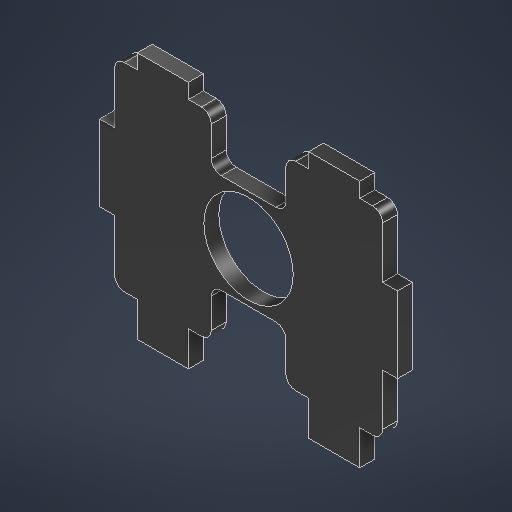
# Autodesk Inventor part: TransmitterFace
Saved by Autodesk Inventor 2027.1 (Build 311270010, 270A)
## iProperties
Created: 2026-10-16
Part Number: TransmitterFace
Material: MDF Medium Density Fiberboard
Document SubType Name: Modeling
Designer: SDS Scholar
Density: 0.8 g/cm^3
Appearance: Glossy - Black
Mass: 5.12957 g
Surface Area: 52.7394 cm^2
Volume: 6.41197 cm^3
Author: SDS Scholar
Autodesk Inventor part; units mm, degrees
ref_plane "YZ Plane" through (0, 0, 0) normal (1, 0, 0) x (0, 1, 0)
ref_plane "XZ Plane" through (0, 0, 0) normal (0, 1, 0) x (-1, 0, 0)
ref_plane "XY Plane" through (0, 0, 0) normal (0, 0, 1) x (1, 0, 0)
sketch "Sketch1" plane through (0, 0, 0) normal (0, 0, 1) x (1, 0, 0)
  line L0 (27, 20) -> (-27, 20)
  line L1 (-27, 20) -> (-27, -20)
  line L2 (-27, -20) -> (27, -20)
  line L3 (27, -20) -> (27, 20)
  circle A0 centre (0, 0) radius 9
  line L4 (7.5, 20) -> (-7.5, 20)
  line L5 (-7.5, 20) -> (-7.5, 10)
  line L6 (-7.5, 10) -> (7.5, 10)
  line L7 (7.5, 10) -> (7.5, 20)
  line L8 (7.5, -20) -> (-7.5, -20)
  line L9 (-7.5, -20) -> (-7.5, -10)
  line L10 (-7.5, -10) -> (7.5, -10)
  line L11 (7.5, -10) -> (7.5, -20)
  line L12 (22.4, 20) -> (12.1, 20)
  line L13 (12.1, 20) -> (12.1, 23)
  line L14 (12.1, 23) -> (22.4, 23)
  line L15 (22.4, 23) -> (22.4, 20)
  line L16 (27, 20) -> (7.5, 20) construction
  line L17 (0, 20) -> (0, -20) construction
  line L18 (22.4, -20) -> (12.1, -20)
  line L19 (12.1, -20) -> (12.1, -27)
  line L20 (12.1, -27) -> (22.4, -27)
  line L21 (22.4, -27) -> (22.4, -20)
  line L22 (27, 7.65) -> (30, 7.65)
  line L23 (30, 7.65) -> (30, -7.65)
  line L24 (30, -7.65) -> (27, -7.65)
  line L25 (27, -7.65) -> (27, 7.65)
  line L26 (-12.1, 20) -> (-12.1, 23)
  line L27 (-12.1, 23) -> (-22.4, 23)
  line L28 (-22.4, 23) -> (-22.4, 20)
  line L29 (-12.1, -20) -> (-12.1, -27)
  line L30 (-12.1, -27) -> (-22.4, -27)
  line L31 (-22.4, -27) -> (-22.4, -20)
  line L32 (-27, 7.65) -> (-30, 7.65)
  line L33 (-30, 7.65) -> (-30, -7.65)
  line L34 (-30, -7.65) -> (-27, -7.65)
  point P0 (-27, 0)
  point P1 (17.25, 23)
  point P2 (17.25, 20)
  point P3 (30, 0)
  point P4 (12.1, -20)
  point P5 (27, -7.65)
  point P6 (12.1, 20)
  point P7 (2.958, 8.5)
  point P8 (2.958, -8.5)
  point P9 (-2.958, -8.5)
  point P10 (-2.958, 8.5)
  point P11 (-12.1, 20)
  point P12 (-22.4, 20)
  point P13 (-27, 7.65)
  point P14 (-27, -7.65)
  point P15 (-22.4, -20)
  point P16 (-12.1, -20)
  point P17 (-7.5, -20)
  point P18 (-17.25, -27)
  point P19 (17.25, -27)
  dimension "d39" = 40
  dimension "d40" = 54
  dimension "d41" = 18
  dimension "d42" = 10
  dimension "d43" = 10
  dimension "d44" = 15
  dimension "d45" = 15
  dimension "d47" = 3
  dimension "d48" = 10.3
  dimension "d49" = 10.3
  dimension "d50" = 7
  dimension "d51" = 15.3
  dimension "d52" = 3
  dimension "d55" = 34.5
  constraints: 70 end point, 12 parallel, 12 symmetric about line, 11 midpoint, 8 perpendicular, 6 horizontal, 6 point on line, 3 vertical alignment, 2 coincident, 2 horizontal alignment, 1 centre point
  measures "d39" distance of L0.end L1.end
  measures "d40" distance of L1.end L2.end
  measures "d41" diameter of A0
  measures "d42" distance of L4.end L5.end
  measures "d43" distance of L8.end L9.end
  measures "d44" distance between parallel lines of L5 L7
  measures "d45" distance between parallel lines of L9 L11
  measures "d47" distance of L14.end L12.start
  measures "d48" distance of L13.end L14.end
  measures "d49" distance of L19.end L20.end
  measures "d50" distance of L20.end L18.start
  measures "d51" distance of L22.end L23.end
  measures "d52" distance of L23.end L24.end
  measures "d55" distance of point (-17.25, -27) point (17.25, -27)
extrude "Extrusion1" add sketch "Sketch1" along normal blind 3 contours L3 L2 L11 L10 L9 L1 L0 L5 L6 L7 | L0 L13 L14 L15 | L22 L23 L24 L3 | L21 L20 L19 L2 | L0 L28 L27 L26 | L1 L34 L33 L32 | L29 L30 L31 L2
fillet "Fillet3" [suppressed]
fillet "Fillet4" radius 2 12 edges at (-7.5, 10, 1.5) (-7.5, 20, 1.5) (7.5, 20, 1.5) (7.5, 10, 1.5) (-27, 20, 1.5) (27, 20, 1.5) (27, -20, 1.5) (7.5, -20, 1.5) (-7.5, -10, 1.5) (7.5, -10, 1.5) (-7.5, -20, 1.5) (-27, -20, 1.5)
equation "\"GridProcutClearance\" = 5"
equation "\"GridBorderThickness\" = 5"
equation "\"GridBorderFillets\" = 7"
equation "\"GridTotalSize\" = 65"
equation "\"GridRobotClearance\" = 65"
equation "\"AluminiumExtrusionClearance\" = 35"
equation "\"BaseTotalLength\" = 885"
equation "\"WorkspaceLength\" = 515"
equation "\"WorkspaceHeight\" = 183"
equation "\"AxesBaseFillet\" = 15"
equation "\"Zaxis\" = 197"
equation "\"ProductTotalHeight\" = 45"
equation "\"VerticalStroke\" = 105"
equation "\"BackArea\" = 165"
equation "\"CylinderStroke\" = 75"
equation "\"BoxesWidth\" = 125"
equation "\"BaseWoodThickness\" = 7"
equation "\"kerf\" = 1.5"
equation "\"Kerf\" = 0.3"
equation "\"RxThickness\" = 1.8"
equation "\"support_2\" = 265"
body "Solid1"
